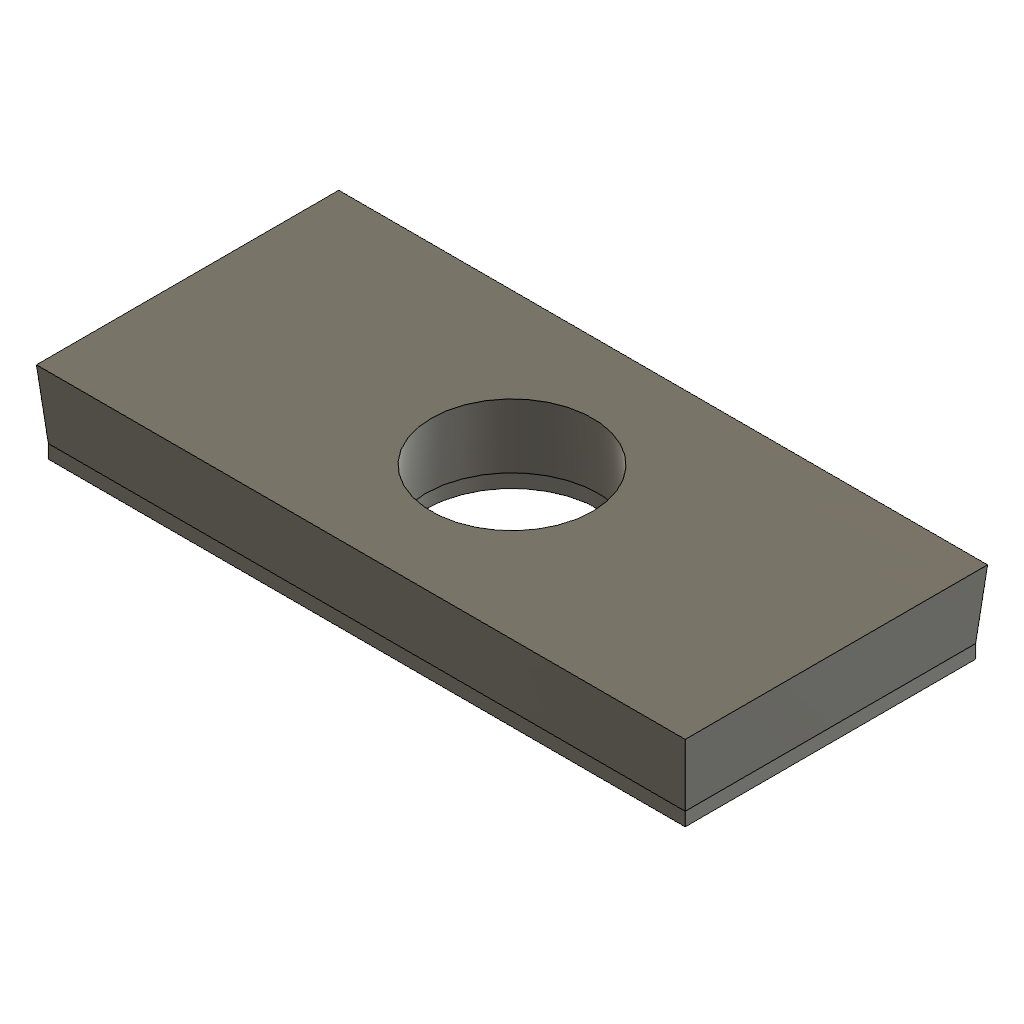
APC Case Feet (Autodesk Fusion 360 design; units mm, degrees)
part number: 2026-10-18-16-57-12-701
Autodesk Fusion 360 part; units mm, degrees
sketch "Sketch1" plane through (0, 0, 0) normal (0, 1, 0) x (1, 0, 0)
  line L0 (25.4, -12.7) -> (-25.4, -12.7) construction
  line L1 (-25.4, -12.7) -> (-25.4, 12.7) construction
  line L2 (-25.4, 12.7) -> (25.4, 12.7) construction
  line L3 (25.4, 12.7) -> (25.4, -12.7) construction
  line L4 (25.4, -12.7) -> (-25.4, 12.7) construction
  line L5 (-25.4, -12.7) -> (25.4, 12.7) construction
  line L6 (23.35, 10.65) -> (-23.35, 10.65)
  line L7 (-23.35, 10.65) -> (-23.35, -10.65)
  line L8 (-23.35, -10.65) -> (23.35, -10.65)
  line L9 (23.35, -10.65) -> (23.35, 10.65)
  line L10 (23.35, 10.65) -> (-23.35, -10.65) construction
  line L11 (-23.35, 10.65) -> (23.35, -10.65) construction
  circle A0 centre (0, 0) radius 6.35
  dimension "d1" = 50.8
  dimension "d2" = 25.4
  dimension "d3" = 46.7
  dimension "d4" = 21.3
  dimension "d5" = 12.7
  constraint horizontal L0
  constraint perpendicular L0 L1
  constraint parallel L0 L2
  constraint parallel L1 L3
  constraint coincident L4 A0.centre
  constraint coincident L5 A0.centre
  constraint coincident A0.centre origin
  constraint horizontal L6
  constraint perpendicular L6 L7
  constraint parallel L6 L8
  constraint parallel L7 L9
  constraint coincident L10 A0.centre
  constraint coincident L11 A0.centre
  measures "d1" distance of L1.end L2.end
  measures "d2" distance of L0.end L1.end
  measures "d3" distance of L7.end L8.end
  measures "d4" distance of L6.end L7.end
  measures "d5" diameter of A0
extrude "Extrude1" add sketch "Sketch1" along normal blind 5 draft 5 and the other way blind 1
equation "d3 = 50.800 mm - 4.1 mm"
equation "d4 = 25.400 mm - 4.1 mm"
